Autodesk Fusion 360 part; units mm, degrees
(part 3 of 11)
  spline S15 degree 5 poles (-18.2968, 31.9705) (-18.3043, 31.9837) (-18.319, 32.0102) (-18.3401, 32.0504) (-18.3664, 32.105) (-18.3968, 32.1744) (-18.4253, 32.2448) (-18.4528, 32.3158) (-18.4796, 32.3871) (-18.5059, 32.4586) (-18.5319, 32.5304) (-18.5573, 32.6024) (-18.5819, 32.6748) (-18.6056, 32.7475) (-18.6285, 32.8208) (-18.6505, 32.8944) (-18.6718, 32.9683) (-18.6925, 33.0425) (-18.7127, 33.1169) (-18.7324, 33.1916) (-18.7516, 33.2664) (-18.7703, 33.3415) (-18.7884, 33.4168) (-18.806, 33.4924) (-18.823, 33.5682) (-18.8394, 33.6442) (-18.8554, 33.7204) (-18.8709, 33.7969) (-18.8859, 33.8735) (-18.9004, 33.9503) (-18.9145, 34.0272) (-18.9281, 34.1044) (-18.9413, 34.1817) (-18.954, 34.2592) (-18.9663, 34.3369) (-18.9781, 34.4148) (-18.9895, 34.4928) (-19.0005, 34.5709) (-19.011, 34.6492) (-19.0211, 34.7277) (-19.0308, 34.8063) (-19.0401, 34.8851) (-19.049, 34.964) (-19.0575, 35.043) (-19.0656, 35.1222) (-19.0732, 35.2015) (-19.0805, 35.281) (-19.0874, 35.3605) (-19.0939, 35.4402) (-19.1, 35.52) (-19.1058, 35.6) (-19.1111, 35.68) (-19.1161, 35.7602) (-19.1207, 35.8405) (-19.1249, 35.9209) (-19.1288, 36.0014) (-19.1323, 36.0821) (-19.1354, 36.1628) (-19.1382, 36.2436) (-19.1406, 36.3246) (-19.1426, 36.4056) (-19.1443, 36.4868) (-19.1456, 36.568) (-19.1466, 36.6493) (-19.1472, 36.7308) (-19.1475, 36.8123) (-19.1474, 36.8939) (-19.147, 36.9756) (-19.1463, 37.0574) (-19.1452, 37.1393) (-19.1437, 37.2212) (-19.1423, 37.2869) (-19.141, 37.3362) (-19.1402, 37.369) (-19.1397, 37.3855) knots 0 0 0 0 0 0 0.01428571 0.02857143 0.04285714 0.05714286 0.07142857 0.08571429 0.1 0.11428571 0.12857143 0.14285714 0.15714286 0.17142857 0.18571429 0.2 0.21428571 0.22857143 0.24285714 0.25714286 0.27142857 0.28571429 0.3 0.31428571 0.32857143 0.34285714 0.35714286 0.37142857 0.38571429 0.4 0.41428571 0.42857143 0.44285714 0.45714286 0.47142857 0.48571429 0.5 0.51428571 0.52857143 0.54285714 0.55714286 0.57142857 0.58571429 0.6 0.61428571 0.62857143 0.64285714 0.65714286 0.67142857 0.68571429 0.7 0.71428571 0.72857143 0.74285714 0.75714286 0.77142857 0.78571429 0.8 0.81428571 0.82857143 0.84285714 0.85714286 0.87142857 0.88571429 0.9 0.91428571 0.92857143 0.94285714 0.95714286 0.97142857 0.98571429 1 1 1 1 1 1
  line L15 (-18.2968, 31.9705) -> (-18.2665, 31.9176)
  arc A30 (-18.6146, 30.5673) -> (-18.2665, 31.9176) centre (-19.1347, 31.4214) ccw
  arc A31 (-18.6146, 30.5673) -> (-19.4636, 30.0339) centre (0, 0) ccw
  arc A32 (-20.8312, 30.3061) -> (-19.4636, 30.0339) centre (-20.0075, 30.8731) ccw
  line L16 (-20.8312, 30.3061) -> (-20.8658, 30.3563)
  spline S16 degree 5 poles (-20.8658, 30.3563) (-20.8744, 30.3688) (-20.8919, 30.3936) (-20.919, 30.43) (-20.9567, 30.4774) (-21.0061, 30.5349) (-21.0571, 30.5912) (-21.1092, 30.6467) (-21.1618, 30.7017) (-21.2148, 30.7566) (-21.2682, 30.8111) (-21.322, 30.8652) (-21.3765, 30.9188) (-21.4318, 30.9717) (-21.4879, 31.0241) (-21.5446, 31.0759) (-21.602, 31.1271) (-21.6599, 31.178) (-21.7182, 31.2284) (-21.7769, 31.2786) (-21.836, 31.3284) (-21.8955, 31.3778) (-21.9555, 31.4268) (-22.016, 31.4754) (-22.0769, 31.5236) (-22.1382, 31.5714) (-22.2, 31.6189) (-22.2621, 31.666) (-22.3247, 31.7127) (-22.3875, 31.7592) (-22.4508, 31.8053) (-22.5144, 31.851) (-22.5783, 31.8964) (-22.6427, 31.9415) (-22.7073, 31.9863) (-22.7723, 32.0307) (-22.8377, 32.0748) (-22.9033, 32.1186) (-22.9693, 32.1621) (-23.0356, 32.2052) (-23.1023, 32.2481) (-23.1692, 32.2906) (-23.2364, 32.3329) (-23.3039, 32.3748) (-23.3718, 32.4164) (-23.4399, 32.4578) (-23.5083, 32.4988) (-23.577, 32.5395) (-23.646, 32.58) (-23.7153, 32.6201) (-23.7848, 32.66) (-23.8546, 32.6995) (-23.9247, 32.7388) (-23.995, 32.7778) (-24.0656, 32.8165) (-24.1365, 32.8549) (-24.2076, 32.893) (-24.279, 32.9309) (-24.3506, 32.9684) (-24.4225, 33.0057) (-24.4947, 33.0427) (-24.567, 33.0794) (-24.6397, 33.1159) (-24.7125, 33.1521) (-24.7856, 33.188) (-24.8589, 33.2236) (-24.9325, 33.2589) (-25.0063, 33.294) (-25.0803, 33.3288) (-25.1546, 33.3633) (-25.229, 33.3976) (-25.2888, 33.4248) (-25.3337, 33.445) (-25.3637, 33.4585) (-25.3787, 33.4652) knots 0 0 0 0 0 0 0.01428571 0.02857143 0.04285714 0.05714286 0.07142857 0.08571429 0.1 0.11428571 0.12857143 0.14285714 0.15714286 0.17142857 0.18571429 0.2 0.21428571 0.22857143 0.24285714 0.25714286 0.27142857 0.28571429 0.3 0.31428571 0.32857143 0.34285714 0.35714286 0.37142857 0.38571429 0.4 0.41428571 0.42857143 0.44285714 0.45714286 0.47142857 0.48571429 0.5 0.51428571 0.52857143 0.54285714 0.55714286 0.57142857 0.58571429 0.6 0.61428571 0.62857143 0.64285714 0.65714286 0.67142857 0.68571429 0.7 0.71428571 0.72857143 0.74285714 0.75714286 0.77142857 0.78571429 0.8 0.81428571 0.82857143 0.84285714 0.85714286 0.87142857 0.88571429 0.9 0.91428571 0.92857143 0.94285714 0.95714286 0.97142857 0.98571429 1 1 1 1 1 1
  arc A33 (-25.3787, 33.4652) -> (-26.9789, 32.1891) centre (0, 0) ccw
  spline S17 degree 5 poles (-24.9521, 27.0976) (-24.9624, 27.1087) (-24.9826, 27.1313) (-25.0122, 27.1658) (-25.05, 27.2131) (-25.095, 27.2741) (-25.1385, 27.3364) (-25.1811, 27.3995) (-25.223, 27.463) (-25.2647, 27.5269) (-25.306, 27.591) (-25.3467, 27.6556) (-25.3868, 27.7207) (-25.4262, 27.7864) (-25.4647, 27.8526) (-25.5026, 27.9195) (-25.5398, 27.9868) (-25.5765, 28.0546) (-25.6127, 28.1226) (-25.6485, 28.191) (-25.6839, 28.2597) (-25.7188, 28.3288) (-25.7533, 28.3982) (-25.7872, 28.4679) (-25.8207, 28.538) (-25.8536, 28.6085) (-25.8862, 28.6793) (-25.9182, 28.7503) (-25.9499, 28.8217) (-25.9812, 28.8933) (-26.0121, 28.9652) (-26.0425, 29.0374) (-26.0726, 29.1099) (-26.1022, 29.1826) (-26.1315, 29.2556) (-26.1603, 29.3289) (-26.1888, 29.4024) (-26.2168, 29.4762) (-26.2445, 29.5502) (-26.2719, 29.6244) (-26.2988, 29.6989) (-26.3254, 29.7736) (-26.3516, 29.8486) (-26.3775, 29.9237) (-26.403, 29.9991) (-26.4281, 30.0747) (-26.4529, 30.1506) (-26.4773, 30.2266) (-26.5014, 30.3029) (-26.5251, 30.3793) (-26.5485, 30.456) (-26.5715, 30.5328) (-26.5942, 30.6099) (-26.6166, 30.6872) (-26.6386, 30.7646) (-26.6603, 30.8422) (-26.6816, 30.9201) (-26.7026, 30.9981) (-26.7233, 31.0763) (-26.7437, 31.1547) (-26.7637, 31.2332) (-26.7834, 31.312) (-26.8028, 31.3909) (-26.8218, 31.4699) (-26.8405, 31.5492) (-26.859, 31.6286) (-26.877, 31.7082) (-26.8948, 31.7879) (-26.9123, 31.8679) (-26.9294, 31.9479) (-26.9462, 32.0282) (-26.9594, 32.0925) (-26.9692, 32.1408) (-26.9757, 32.173) (-26.9789, 32.1891) knots 0 0 0 0 0 0 0.01428571 0.02857143 0.04285714 0.05714286 0.07142857 0.08571429 0.1 0.11428571 0.12857143 0.14285714 0.15714286 0.17142857 0.18571429 0.2 0.21428571 0.22857143 0.24285714 0.25714286 0.27142857 0.28571429 0.3 0.31428571 0.32857143 0.34285714 0.35714286 0.37142857 0.38571429 0.4 0.41428571 0.42857143 0.44285714 0.45714286 0.47142857 0.48571429 0.5 0.51428571 0.52857143 0.54285714 0.55714286 0.57142857 0.58571429 0.6 0.61428571 0.62857143 0.64285714 0.65714286 0.67142857 0.68571429 0.7 0.71428571 0.72857143 0.74285714 0.75714286 0.77142857 0.78571429 0.8 0.81428571 0.82857143 0.84285714 0.85714286 0.87142857 0.88571429 0.9 0.91428571 0.92857143 0.94285714 0.95714286 0.97142857 0.98571429 1 1 1 1 1 1
  line L17 (-24.9521, 27.0976) -> (-24.9108, 27.0527)
  arc A34 (-24.9498, 25.6588) -> (-24.9108, 27.0527) centre (-25.6469, 26.3758) ccw
  arc A35 (-24.9498, 25.6588) -> (-25.6588, 24.9498) centre (0, 0) ccw
  arc A36 (-27.0527, 24.9108) -> (-25.6588, 24.9498) centre (-26.3758, 25.6469) ccw
  line L18 (-27.0527, 24.9108) -> (-27.0976, 24.9521)
  spline S18 degree 5 poles (-27.0976, 24.9521) (-27.1087, 24.9624) (-27.1313, 24.9826) (-27.1658, 25.0122) (-27.2131, 25.05) (-27.2741, 25.095) (-27.3364, 25.1385) (-27.3995, 25.1811) (-27.463, 25.223) (-27.5269, 25.2647) (-27.591, 25.306) (-27.6556, 25.3467) (-27.7207, 25.3868) (-27.7864, 25.4262) (-27.8526, 25.4647) (-27.9195, 25.5026) (-27.9868, 25.5398) (-28.0546, 25.5765) (-28.1226, 25.6127) (-28.191, 25.6485) (-28.2597, 25.6839) (-28.3288, 25.7188) (-28.3982, 25.7533) (-28.4679, 25.7872) (-28.538, 25.8207) (-28.6085, 25.8536) (-28.6793, 25.8862) (-28.7503, 25.9182) (-28.8217, 25.9499) (-28.8933, 25.9812) (-28.9652, 26.0121) (-29.0374, 26.0425) (-29.1099, 26.0726) (-29.1826, 26.1022) (-29.2556, 26.1315) (-29.3289, 26.1603) (-29.4024, 26.1888) (-29.4762, 26.2168) (-29.5502, 26.2445) (-29.6244, 26.2719) (-29.6989, 26.2988) (-29.7736, 26.3254) (-29.8486, 26.3516) (-29.9237, 26.3775) (-29.9991, 26.403) (-30.0747, 26.4281) (-30.1506, 26.4529) (-30.2266, 26.4773) (-30.3029, 26.5014) (-30.3793, 26.5251) (-30.456, 26.5485) (-30.5328, 26.5715) (-30.6099, 26.5942) (-30.6872, 26.6166) (-30.7646, 26.6386) (-30.8422, 26.6603) (-30.9201, 26.6816) (-30.9981, 26.7026) (-31.0763, 26.7233) (-31.1547, 26.7437) (-31.2332, 26.7637) (-31.312, 26.7834) (-31.3909, 26.8028) (-31.4699, 26.8218) (-31.5492, 26.8405) (-31.6286, 26.859) (-31.7082, 26.877) (-31.7879, 26.8948) (-31.8679, 26.9123) (-31.9479, 26.9294) (-32.0282, 26.9462) (-32.0925, 26.9594) (-32.1408, 26.9692) (-32.173, 26.9757) (-32.1891, 26.9789) knots 0 0 0 0 0 0 0.01428571 0.02857143 0.04285714 0.05714286 0.07142857 0.08571429 0.1 0.11428571 0.12857143 0.14285714 0.15714286 0.17142857 0.18571429 0.2 0.21428571 0.22857143 0.24285714 0.25714286 0.27142857 0.28571429 0.3 0.31428571 0.32857143 0.34285714 0.35714286 0.37142857 0.38571429 0.4 0.41428571 0.42857143 0.44285714 0.45714286 0.47142857 0.48571429 0.5 0.51428571 0.52857143 0.54285714 0.55714286 0.57142857 0.58571429 0.6 0.61428571 0.62857143 0.64285714 0.65714286 0.67142857 0.68571429 0.7 0.71428571 0.72857143 0.74285714 0.75714286 0.77142857 0.78571429 0.8 0.81428571 0.82857143 0.84285714 0.85714286 0.87142857 0.88571429 0.9 0.91428571 0.92857143 0.94285714 0.95714286 0.97142857 0.98571429 1 1 1 1 1 1
  arc A37 (-32.1891, 26.9789) -> (-33.4652, 25.3787) centre (0, 0) ccw
  spline S19 degree 5 poles (-30.3563, 20.8658) (-30.3688, 20.8744) (-30.3936, 20.8919) (-30.43, 20.919) (-30.4774, 20.9567) (-30.5349, 21.0061) (-30.5912, 21.0571) (-30.6467, 21.1092) (-30.7017, 21.1618) (-30.7566, 21.2148) (-30.8111, 21.2682) (-30.8652, 21.322) (-30.9188, 21.3765) (-30.9717, 21.4318) (-31.0241, 21.4879) (-31.0759, 21.5446) (-31.1271, 21.602) (-31.178, 21.6599) (-31.2284, 21.7182) (-31.2786, 21.7769) (-31.3284, 21.836) (-31.3778, 21.8955) (-31.4268, 21.9555) (-31.4754, 22.016) (-31.5236, 22.0769) (-31.5714, 22.1382) (-31.6189, 22.2) (-31.666, 22.2621) (-31.7127, 22.3247) (-31.7592, 22.3875) (-31.8053, 22.4508) (-31.851, 22.5144) (-31.8964, 22.5783) (-31.9415, 22.6427) (-31.9863, 22.7073) (-32.0307, 22.7723) (-32.0748, 22.8377) (-32.1186, 22.9033) (-32.1621, 22.9693) (-32.2052, 23.0356) (-32.2481, 23.1023) (-32.2906, 23.1692) (-32.3329, 23.2364) (-32.3748, 23.3039) (-32.4164, 23.3718) (-32.4578, 23.4399) (-32.4988, 23.5083) (-32.5395, 23.577) (-32.58, 23.646) (-32.6201, 23.7153) (-32.66, 23.7848) (-32.6995, 23.8546) (-32.7388, 23.9247) (-32.7778, 23.995) (-32.8165, 24.0656) (-32.8549, 24.1365) (-32.893, 24.2076) (-32.9309, 24.279) (-32.9684, 24.3506) (-33.0057, 24.4225) (-33.0427, 24.4947) (-33.0794, 24.567) (-33.1159, 24.6397) (-33.1521, 24.7125) (-33.188, 24.7856) (-33.2236, 24.8589) (-33.2589, 24.9325) (-33.294, 25.0063) (-33.3288, 25.0803) (-33.3633, 25.1546) (-33.3976, 25.229) (-33.4248, 25.2888) (-33.445, 25.3337) (-33.4585, 25.3637) (-33.4652, 25.3787) knots 0 0 0 0 0 0 0.01428571 0.02857143 0.04285714 0.05714286 0.07142857 0.08571429 0.1 0.11428571 0.12857143 0.14285714 0.15714286 0.17142857 0.18571429 0.2 0.21428571 0.22857143 0.24285714 0.25714286 0.27142857 0.28571429 0.3 0.31428571 0.32857143 0.34285714 0.35714286 0.37142857 0.38571429 0.4 0.41428571 0.42857143 0.44285714 0.45714286 0.47142857 0.48571429 0.5 0.51428571 0.52857143 0.54285714 0.55714286 0.57142857 0.58571429 0.6 0.61428571 0.62857143 0.64285714 0.65714286 0.67142857 0.68571429 0.7 0.71428571 0.72857143 0.74285714 0.75714286 0.77142857 0.78571429 0.8 0.81428571 0.82857143 0.84285714 0.85714286 0.87142857 0.88571429 0.9 0.91428571 0.92857143 0.94285714 0.95714286 0.97142857 0.98571429 1 1 1 1 1 1
  line L19 (-30.3563, 20.8658) -> (-30.3061, 20.8312)
  arc A38 (-30.0339, 19.4636) -> (-30.3061, 20.8312) centre (-30.8731, 20.0075) ccw
  arc A39 (-30.0339, 19.4636) -> (-30.5673, 18.6146) centre (0, 0) ccw
  arc A40 (-31.9176, 18.2665) -> (-30.5673, 18.6146) centre (-31.4214, 19.1347) ccw
  line L20 (-31.9176, 18.2665) -> (-31.9705, 18.2968)
  spline S20 degree 5 poles (-31.9705, 18.2968) (-31.9837, 18.3043) (-32.0102, 18.319) (-32.0504, 18.3401) (-32.105, 18.3664) (-32.1744, 18.3968) (-32.2448, 18.4253) (-32.3158, 18.4528) (-32.3871, 18.4796) (-32.4586, 18.5059) (-32.5304, 18.5319) (-32.6024, 18.5573) (-32.6748, 18.5819) (-32.7475, 18.6056) (-32.8208, 18.6285) (-32.8944, 18.6505) (-32.9683, 18.6718) (-33.0425, 18.6925) (-33.1169, 18.7127) (-33.1916, 18.7324) (-33.2664, 18.7516) (-33.3415, 18.7703) (-33.4168, 18.7884) (-33.4924, 18.806) (-33.5682, 18.823) (-33.6442, 18.8394) (-33.7204, 18.8554) (-33.7969, 18.8709) (-33.8735, 18.8859) (-33.9503, 18.9004) (-34.0272, 18.9145) (-34.1044, 18.9281) (-34.1817, 18.9413) (-34.2592, 18.954) (-34.3369, 18.9663) (-34.4148, 18.9781) (-34.4928, 18.9895) (-34.5709, 19.0005) (-34.6492, 19.011) (-34.7277, 19.0211) (-34.8063, 19.0308) (-34.8851, 19.0401) (-34.964, 19.049) (-35.043, 19.0575) (-35.1222, 19.0656) (-35.2015, 19.0732) (-35.281, 19.0805) (-35.3605, 19.0874) (-35.4402, 19.0939) (-35.52, 19.1) (-35.6, 19.1058) (-35.68, 19.1111) (-35.7602, 19.1161) (-35.8405, 19.1207) (-35.9209, 19.1249) (-36.0014, 19.1288) (-36.0821, 19.1323) (-36.1628, 19.1354) (-36.2436, 19.1382) (-36.3246, 19.1406) (-36.4056, 19.1426) (-36.4868, 19.1443) (-36.568, 19.1456) (-36.6493, 19.1466) (-36.7308, 19.1472) (-36.8123, 19.1475) (-36.8939, 19.1474) (-36.9756, 19.147) (-37.0574, 19.1463) (-37.1393, 19.1452) (-37.2212, 19.1437) (-37.2869, 19.1423) (-37.3362, 19.141) (-37.369, 19.1402) (-37.3855, 19.1397) knots 0 0 0 0 0 0 0.01428571 0.02857143 0.04285714 0.05714286 0.07142857 0.08571429 0.1 0.11428571 0.12857143 0.14285714 0.15714286 0.17142857 0.18571429 0.2 0.21428571 0.22857143 0.24285714 0.25714286 0.27142857 0.28571429 0.3 0.31428571 0.32857143 0.34285714 0.35714286 0.37142857 0.38571429 0.4 0.41428571 0.42857143 0.44285714 0.45714286 0.47142857 0.48571429 0.5 0.51428571 0.52857143 0.54285714 0.55714286 0.57142857 0.58571429 0.6 0.61428571 0.62857143 0.64285714 0.65714286 0.67142857 0.68571429 0.7 0.71428571 0.72857143 0.74285714 0.75714286 0.77142857 0.78571429 0.8 0.81428571 0.82857143 0.84285714 0.85714286 0.87142857 0.88571429 0.9 0.91428571 0.92857143 0.94285714 0.95714286 0.97142857 0.98571429 1 1 1 1 1 1
  arc A41 (-37.3855, 19.1397) -> (-38.2735, 17.2957) centre (0, 0) ccw
  spline S21 degree 5 poles (-34.2383, 13.5877) (-34.2524, 13.5933) (-34.2804, 13.6049) (-34.322, 13.6232) (-34.3766, 13.6494) (-34.4436, 13.6848) (-34.5098, 13.722) (-34.5755, 13.7604) (-34.6409, 13.7995) (-34.7062, 13.8389) (-34.7712, 13.8788) (-34.8359, 13.9193) (-34.9003, 13.9605) (-34.9642, 14.0026) (-35.0278, 14.0456) (-35.0909, 14.0894) (-35.1536, 14.134) (-35.2161, 14.1791) (-35.2782, 14.2247) (-35.3402, 14.2708) (-35.4019, 14.3173) (-35.4633, 14.3644) (-35.5244, 14.412) (-35.5852, 14.4601) (-35.6458, 14.5087) (-35.7061, 14.5579) (-35.7661, 14.6075) (-35.8258, 14.6576) (-35.8853, 14.7082) (-35.9446, 14.7592) (-36.0036, 14.8106) (-36.0624, 14.8624) (-36.1209, 14.9146) (-36.1791, 14.9673) (-36.2372, 15.0204) (-36.295, 15.0739) (-36.3525, 15.1278) (-36.4098, 15.182) (-36.4669, 15.2367) (-36.5237, 15.2917) (-36.5803, 15.3472) (-36.6367, 15.4029) (-36.6928, 15.4591) (-36.7487, 15.5156) (-36.8044, 15.5725) (-36.8598, 15.6297) (-36.9151, 15.6872) (-36.9701, 15.7452) (-37.0248, 15.8034) (-37.0794, 15.862) (-37.1337, 15.9209) (-37.1878, 15.9802) (-37.2417, 16.0398) (-37.2954, 16.0997) (-37.3488, 16.1599) (-37.402, 16.2204) (-37.455, 16.2813) (-37.5078, 16.3425) (-37.5604, 16.404) (-37.6127, 16.4657) (-37.6648, 16.5278) (-37.7168, 16.5902) (-37.7684, 16.6529) (-37.8199, 16.7159) (-37.8712, 16.7792) (-37.9222, 16.8427) (-37.9731, 16.9066) (-38.0237, 16.9707) (-38.0741, 17.0352) (-38.1243, 17.0999) (-38.1742, 17.1648) (-38.214, 17.2171) (-38.2438, 17.2563) (-38.2636, 17.2826) (-38.2735, 17.2957) knots 0 0 0 0 0 0 0.01428571 0.02857143 0.04285714 0.05714286 0.07142857 0.08571429 0.1 0.11428571 0.12857143 0.14285714 0.15714286 0.17142857 0.18571429 0.2 0.21428571 0.22857143 0.24285714 0.25714286 0.27142857 0.28571429 0.3 0.31428571 0.32857143 0.34285714 0.35714286 0.37142857 0.38571429 0.4 0.41428571 0.42857143 0.44285714 0.45714286 0.47142857 0.48571429 0.5 0.51428571 0.52857143 0.54285714 0.55714286 0.57142857 0.58571429 0.6 0.61428571 0.62857143 0.64285714 0.65714286 0.67142857 0.68571429 0.7 0.71428571 0.72857143 0.74285714 0.75714286 0.77142857 0.78571429 0.8 0.81428571 0.82857143 0.84285714 0.85714286 0.87142857 0.88571429 0.9 0.91428571 0.92857143 0.94285714 0.95714286 0.97142857 0.98571429 1 1 1 1 1 1
  line L21 (-34.2383, 13.5877) -> (-34.1816, 13.5652)
  arc A42 (-33.6119, 12.2925) -> (-34.1816, 13.5652) centre (-34.5511, 12.636) ccw
  arc A43 (-33.6119, 12.2925) -> (-33.9431, 11.346) centre (0, 0) ccw
  arc A44 (-35.182, 10.7062) -> (-33.9431, 11.346) centre (-34.8915, 11.6631) ccw
  line L22 (-35.182, 10.7062) -> (-35.2404, 10.7239)
  spline S22 degree 5 poles (-35.2404, 10.7239) (-35.2549, 10.7283) (-35.284, 10.7368) (-35.3279, 10.7484) (-35.3869, 10.7619) (-35.4614, 10.7761) (-35.5364, 10.7882) (-35.6117, 10.7992) (-35.6872, 10.8094) (-35.7628, 10.8192) (-35.8385, 10.8286) (-35.9144, 10.8373) (-35.9904, 10.8452) (-36.0666, 10.8522) (-36.1431, 10.8581) (-36.2198, 10.8632) (-36.2966, 10.8675) (-36.3735, 10.8712) (-36.4506, 10.8743) (-36.5277, 10.8769) (-36.605, 10.879) (-36.6823, 10.8805) (-36.7598, 10.8814) (-36.8374, 10.8817) (-36.9151, 10.8814) (-36.9928, 10.8806) (-37.0707, 10.8792) (-37.1487, 10.8772) (-37.2267, 10.8748) (-37.3048, 10.8719) (-37.383, 10.8685) (-37.4612, 10.8646) (-37.5396, 10.8603) (-37.618, 10.8554) (-37.6964, 10.8501) (-37.7749, 10.8443) (-37.8535, 10.838) (-37.9322, 10.8313) (-38.0109, 10.8242) (-38.0896, 10.8166) (-38.1684, 10.8086) (-38.2473, 10.8001) (-38.3262, 10.7912) (-38.4051, 10.7819) (-38.4841, 10.7721) (-38.5631, 10.762) (-38.6422, 10.7514) (-38.7213, 10.7404) (-38.8005, 10.729) (-38.8796, 10.7172) (-38.9589, 10.705) (-39.0381, 10.6924) (-39.1174, 10.6794) (-39.1967, 10.666) (-39.276, 10.6523) (-39.3554, 10.6381) (-39.4347, 10.6236) (-39.5142, 10.6087) (-39.5936, 10.5934) (-39.673, 10.5777) (-39.7525, 10.5617) (-39.832, 10.5453) (-39.9115, 10.5285) (-39.991, 10.5113) (-40.0705, 10.4938) (-40.1501, 10.4759) (-40.2296, 10.4577) (-40.3092, 10.4391) (-40.3887, 10.4202) (-40.4683, 10.4009) (-40.5479, 10.3812) (-40.6116, 10.3652) (-40.6593, 10.3531) (-40.6912, 10.3449) (-40.7071, 10.3408) knots 0 0 0 0 0 0 0.01428571 0.02857143 0.04285714 0.05714286 0.07142857 0.08571429 0.1 0.11428571 0.12857143 0.14285714 0.15714286 0.17142857 0.18571429 0.2 0.21428571 0.22857143 0.24285714 0.25714286 0.27142857 0.28571429 0.3 0.31428571 0.32857143 0.34285714 0.35714286 0.37142857 0.38571429 0.4 0.41428571 0.42857143 0.44285714 0.45714286 0.47142857 0.48571429 0.5 0.51428571 0.52857143 0.54285714 0.55714286 0.57142857 0.58571429 0.6 0.61428571 0.62857143 0.64285714 0.65714286 0.67142857 0.68571429 0.7 0.71428571 0.72857143 0.74285714 0.75714286 0.77142857 0.78571429 0.8 0.81428571 0.82857143 0.84285714 0.85714286 0.87142857 0.88571429 0.9 0.91428571 0.92857143 0.94285714 0.95714286 0.97142857 0.98571429 1 1 1 1 1 1
  arc A45 (-40.7071, 10.3408) -> (-41.1625, 8.3454) centre (0, 0) ccw
  spline S23 degree 5 poles (-36.4034, 5.6283) (-36.4184, 5.6307) (-36.4483, 5.6357) (-36.4929, 5.6442) (-36.552, 5.6577) (-36.6252, 5.6772) (-36.698, 5.6988) (-36.7706, 5.7216) (-36.8431, 5.7451) (-36.9154, 5.7691) (-36.9877, 5.7935) (-37.0598, 5.8186) (-37.1318, 5.8445) (-37.2035, 5.8713) (-37.275, 5.8991) (-37.3463, 5.9277) (-37.4173, 5.9572) (-37.4883, 5.9873) (-37.559, 6.0179) (-37.6297, 6.049) (-37.7002, 6.0807) (-37.7705, 6.1129) (-37.8407, 6.1457) (-37.9107, 6.1791) (-37.9806, 6.213) (-38.0503, 6.2475) (-38.1198, 6.2826) (-38.1892, 6.3182) (-38.2585, 6.3542) (-38.3276, 6.3907) (-38.3966, 6.4277) (-38.4654, 6.4651) (-38.5341, 6.503) (-38.6026, 6.5414) (-38.671, 6.5803) (-38.7392, 6.6196) (-38.8073, 6.6593) (-38.8752, 6.6995) (-38.943, 6.74) (-39.0107, 6.7811) (-39.0782, 6.8225) (-39.1456, 6.8643) (-39.2128, 6.9066) (-39.2799, 6.9492) (-39.3468, 6.9923) (-39.4136, 7.0357) (-39.4803, 7.0796) (-39.5468, 7.1238) (-39.6131, 7.1684) (-39.6794, 7.2134) (-39.7454, 7.2587) (-39.8114, 7.3045) (-39.8772, 7.3506) (-39.9428, 7.397) (-40.0083, 7.4438) (-40.0737, 7.491) (-40.1389, 7.5386) (-40.204, 7.5865) (-40.2689, 7.6347) (-40.3337, 7.6833) (-40.3983, 7.7322) (-40.4628, 7.7815) (-40.5271, 7.8311) (-40.5913, 7.8811) (-40.6554, 7.9313) (-40.7193, 7.982) (-40.7831, 8.0329) (-40.8467, 8.0842) (-40.9101, 8.1358) (-40.9735, 8.1877) (-41.0366, 8.2399) (-41.0871, 8.282) (-41.1248, 8.3136) (-41.15, 8.3348) (-41.1625, 8.3454) knots 0 0 0 0 0 0 0.01428571 0.02857143 0.04285714 0.05714286 0.07142857 0.08571429 0.1 0.11428571 0.12857143 0.14285714 0.15714286 0.17142857 0.18571429 0.2 0.21428571 0.22857143 0.24285714 0.25714286 0.27142857 0.28571429 0.3 0.31428571 0.32857143 0.34285714 0.35714286 0.37142857 0.38571429 0.4 0.41428571 0.42857143 0.44285714 0.45714286 0.47142857 0.48571429 0.5 0.51428571 0.52857143 0.54285714 0.55714286 0.57142857 0.58571429 0.6 0.61428571 0.62857143 0.64285714 0.65714286 0.67142857 0.68571429 0.7 0.71428571 0.72857143 0.74285714 0.75714286 0.77142857 0.78571429 0.8 0.81428571 0.82857143 0.84285714 0.85714286 0.87142857 0.88571429 0.9 0.91428571 0.92857143 0.94285714 0.95714286 0.97142857 0.98571429 1 1 1 1 1 1
  line L23 (-36.4034, 5.6283) -> (-36.3431, 5.619)
  arc A46 (-35.5045, 4.5049) -> (-36.3431, 5.619) centre (-36.4966, 4.6308) ccw
  arc A47 (-35.5045, 4.5049) -> (-35.6168, 3.5085) centre (0, 0) ccw
  arc A48 (-36.6823, 2.609) -> (-35.6168, 3.5085) centre (-36.612, 3.6066) ccw
  line L24 (-36.6823, 2.609) -> (-36.7431, 2.6133)
  spline S24 degree 5 poles (-36.7431, 2.6133) (-36.7583, 2.6144) (-36.7885, 2.6161) (-36.8339, 2.6177) (-36.8945, 2.6178) (-36.9702, 2.615) (-37.0461, 2.6101) (-37.1219, 2.6041) (-37.1978, 2.5973) (-37.2736, 2.59) (-37.3495, 2.5823) (-37.4254, 2.5739) (-37.5013, 2.5647) (-37.5772, 2.5545) (-37.6531, 2.5433) (-37.7289, 2.5312) (-37.8048, 2.5183) (-37.8806, 2.5048) (-37.9564, 2.4907) (-38.0322, 2.476) (-38.108, 2.4608) (-38.1838, 2.4451) (-38.2595, 2.4287) (-38.3352, 2.4118) (-38.4109, 2.3942) (-38.4865, 2.3761) (-38.5621, 2.3574) (-38.6377, 2.3382) (-38.7132, 2.3184) (-38.7887, 2.2982) (-38.8642, 2.2775) (-38.9396, 2.2563) (-39.015, 2.2346) (-39.0904, 2.2125) (-39.1657, 2.1898) (-39.2409, 2.1667) (-39.3162, 2.1431) (-39.3913, 2.1191) (-39.4665, 2.0946) (-39.5415, 2.0697) (-39.6166, 2.0443) (-39.6916, 2.0185) (-39.7665, 1.9923) (-39.8414, 1.9656) (-39.9162, 1.9385) (-39.991, 1.911) (-40.0658, 1.8831) (-40.1405, 1.8548) (-40.2151, 1.8261) (-40.2896, 1.797) (-40.3642, 1.7675) (-40.4386, 1.7375) (-40.513, 1.7072) (-40.5874, 1.6765) (-40.6616, 1.6455) (-40.7359, 1.614) (-40.81, 1.5822) (-40.8841, 1.55) (-40.9581, 1.5174) (-41.0321, 1.4844) (-41.106, 1.4511) (-41.1798, 1.4174) (-41.2536, 1.3834) (-41.3273, 1.349) (-41.401, 1.3142) (-41.4745, 1.2791) (-41.548, 1.2436) (-41.6215, 1.2078) (-41.6948, 1.1716) (-41.7681, 1.1351) (-41.8413, 1.0982) (-41.8998, 1.0684) (-41.9437, 1.0459) (-41.9729, 1.0309) (-41.9875, 1.0233) knots 0 0 0 0 0 0 0.01428571 0.02857143 0.04285714 0.05714286 0.07142857 0.08571429 0.1 0.11428571 0.12857143 0.14285714 0.15714286 0.17142857 0.18571429 0.2 0.21428571 0.22857143 0.24285714 0.25714286 0.27142857 0.28571429 0.3 0.31428571 0.32857143 0.34285714 0.35714286 0.37142857 0.38571429 0.4 0.41428571 0.42857143 0.44285714 0.45714286 0.47142857 0.48571429 0.5 0.51428571 0.52857143 0.54285714 0.55714286 0.57142857 0.58571429 0.6 0.61428571 0.62857143 0.64285714 0.65714286 0.67142857 0.68571429 0.7 0.71428571 0.72857143 0.74285714 0.75714286 0.77142857 0.78571429 0.8 0.81428571 0.82857143 0.84285714 0.85714286 0.87142857 0.88571429 0.9 0.91428571 0.92857143 0.94285714 0.95714286 0.97142857 0.98571429 1 1 1 1 1 1
  arc A49 (-41.9875, 1.0233) -> (-41.9875, -1.0233) centre (0, 0) ccw
  spline S25 degree 5 poles (-36.7431, -2.6133) (-36.7583, -2.6144) (-36.7885, -2.6161) (-36.8339, -2.6177) (-36.8945, -2.6178) (-36.9702, -2.615) (-37.0461, -2.6101) (-37.1219, -2.6041) (-37.1978, -2.5973) (-37.2736, -2.59) (-37.3495, -2.5823) (-37.4254, -2.5739) (-37.5013, -2.5647) (-37.5772, -2.5545) (-37.6531, -2.5433) (-37.7289, -2.5312) (-37.8048, -2.5183) (-37.8806, -2.5048) (-37.9564, -2.4907) (-38.0322, -2.476) (-38.108, -2.4608) (-38.1838, -2.4451) (-38.2595, -2.4287) (-38.3352, -2.4118) (-38.4109, -2.3942) (-38.4865, -2.3761) (-38.5621, -2.3574) (-38.6377, -2.3382) (-38.7132, -2.3184) (-38.7887, -2.2982) (-38.8642, -2.2775) (-38.9396, -2.2563) (-39.015, -2.2346) (-39.0904, -2.2125) (-39.1657, -2.1898) (-39.2409, -2.1667) (-39.3162, -2.1431) (-39.3913, -2.1191) (-39.4665, -2.0946) (-39.5415, -2.0697) (-39.6166, -2.0443) (-39.6916, -2.0185) (-39.7665, -1.9923) (-39.8414, -1.9656) (-39.9162, -1.9385) (-39.991, -1.911) (-40.0658, -1.8831) (-40.1405, -1.8548) (-40.2151, -1.8261) (-40.2896, -1.797) (-40.3642, -1.7675) (-40.4386, -1.7375) (-40.513, -1.7072) (-40.5874, -1.6765) (-40.6616, -1.6455) (-40.7359, -1.614) (-40.81, -1.5822) (-40.8841, -1.55) (-40.9581, -1.5174) (-41.0321, -1.4844) (-41.106, -1.4511) (-41.1798, -1.4174) (-41.2536, -1.3834) (-41.3273, -1.349) (-41.401, -1.3142) (-41.4745, -1.2791) (-41.548, -1.2436) (-41.6215, -1.2078) (-41.6948, -1.1716) (-41.7681, -1.1351) (-41.8413, -1.0982) (-41.8998, -1.0684) (-41.9437, -1.0459) (-41.9729, -1.0309) (-41.9875, -1.0233) knots 0 0 0 0 0 0 0.01428571 0.02857143 0.04285714 0.05714286 0.07142857 0.08571429 0.1 0.11428571 0.12857143 0.14285714 0.15714286 0.17142857 0.18571429 0.2 0.21428571 0.22857143 0.24285714 0.25714286 0.27142857 0.28571429 0.3 0.31428571 0.32857143 0.34285714 0.35714286 0.37142857 0.38571429 0.4 0.41428571 0.42857143 0.44285714 0.45714286 0.47142857 0.48571429 0.5 0.51428571 0.52857143 0.54285714 0.55714286 0.57142857 0.58571429 0.6 0.61428571 0.62857143 0.64285714 0.65714286 0.67142857 0.68571429 0.7 0.71428571 0.72857143 0.74285714 0.75714286 0.77142857 0.78571429 0.8 0.81428571 0.82857143 0.84285714 0.85714286 0.87142857 0.88571429 0.9 0.91428571 0.92857143 0.94285714 0.95714286 0.97142857 0.98571429 1 1 1 1 1 1
  line L25 (-36.7431, -2.6133) -> (-36.6823, -2.609)
  arc A50 (-35.6168, -3.5085) -> (-36.6823, -2.609) centre (-36.612, -3.6066) ccw
  arc A51 (-35.6168, -3.5085) -> (-35.5045, -4.5049) centre (0, 0) ccw
  arc A52 (-36.3431, -5.619) -> (-35.5045, -4.5049) centre (-36.4966, -4.6308) ccw
  line L26 (-36.3431, -5.619) -> (-36.4034, -5.6283)
  spline S26 degree 5 poles (-36.4034, -5.6283) (-36.4184, -5.6307) (-36.4483, -5.6357) (-36.4929, -5.6442) (-36.552, -5.6577) (-36.6252, -5.6772) (-36.698, -5.6988) (-36.7706, -5.7216) (-36.8431, -5.7451) (-36.9154, -5.7691) (-36.9877, -5.7935) (-37.0598, -5.8186) (-37.1318, -5.8445) (-37.2035, -5.8713) (-37.275, -5.8991) (-37.3463, -5.9277) (-37.4173, -5.9572) (-37.4883, -5.9873) (-37.559, -6.0179) (-37.6297, -6.049) (-37.7002, -6.0807) (-37.7705, -6.1129) (-37.8407, -6.1457) (-37.9107, -6.1791) (-37.9806, -6.213) (-38.0503, -6.2475) (-38.1198, -6.2826) (-38.1892, -6.3182) (-38.2585, -6.3542) (-38.3276, -6.3907) (-38.3966, -6.4277) (-38.4654, -6.4651) (-38.5341, -6.503) (-38.6026, -6.5414) (-38.671, -6.5803) (-38.7392, -6.6196) (-38.8073, -6.6593) (-38.8752, -6.6995) (-38.943, -6.74) (-39.0107, -6.7811) (-39.0782, -6.8225) (-39.1456, -6.8643) (-39.2128, -6.9066) (-39.2799, -6.9492) (-39.3468, -6.9923) (-39.4136, -7.0357) (-39.4803, -7.0796) (-39.5468, -7.1238) (-39.6131, -7.1684) (-39.6794, -7.2134) (-39.7454, -7.2587) (-39.8114, -7.3045) (-39.8772, -7.3506) (-39.9428, -7.397) (-40.0083, -7.4438) (-40.0737, -7.491) (-40.1389, -7.5386) (-40.204, -7.5865) (-40.2689, -7.6347) (-40.3337, -7.6833) (-40.3983, -7.7322) (-40.4628, -7.7815) (-40.5271, -7.8311) (-40.5913, -7.8811) (-40.6554, -7.9313) (-40.7193, -7.982) (-40.7831, -8.0329) (-40.8467, -8.0842) (-40.9101, -8.1358) (-40.9735, -8.1877) (-41.0366, -8.2399) (-41.0871, -8.282) (-41.1248, -8.3136) (-41.15, -8.3348) (-41.1625, -8.3454) knots 0 0 0 0 0 0 0.01428571 0.02857143 0.04285714 0.05714286 0.07142857 0.08571429 0.1 0.11428571 0.12857143 0.14285714 0.15714286 0.17142857 0.18571429 0.2 0.21428571 0.22857143 0.24285714 0.25714286 0.27142857 0.28571429 0.3 0.31428571 0.32857143 0.34285714 0.35714286 0.37142857 0.38571429 0.4 0.41428571 0.42857143 0.44285714 0.45714286 0.47142857 0.48571429 0.5 0.51428571 0.52857143 0.54285714 0.55714286 0.57142857 0.58571429 0.6 0.61428571 0.62857143 0.64285714 0.65714286 0.67142857 0.68571429 0.7 0.71428571 0.72857143 0.74285714 0.75714286 0.77142857 0.78571429 0.8 0.81428571 0.82857143 0.84285714 0.85714286 0.87142857 0.88571429 0.9 0.91428571 0.92857143 0.94285714 0.95714286 0.97142857 0.98571429 1 1 1 1 1 1
  arc A53 (-41.1625, -8.3454) -> (-40.7071, -10.3408) centre (0, 0) ccw
  spline S27 degree 5 poles (-35.2404, -10.7239) (-35.2549, -10.7283) (-35.284, -10.7368) (-35.3279, -10.7484) (-35.3869, -10.7619) (-35.4614, -10.7761) (-35.5364, -10.7882) (-35.6117, -10.7992) (-35.6872, -10.8094) (-35.7628, -10.8192) (-35.8385, -10.8286) (-35.9144, -10.8373) (-35.9904, -10.8452) (-36.0666, -10.8522) (-36.1431, -10.8581) (-36.2198, -10.8632) (-36.2966, -10.8675) (-36.3735, -10.8712) (-36.4506, -10.8743) (-36.5277, -10.8769) (-36.605, -10.879) (-36.6823, -10.8805) (-36.7598, -10.8814) (-36.8374, -10.8817) (-36.9151, -10.8814) (-36.9928, -10.8806) (-37.0707, -10.8792) (-37.1487, -10.8772) (-37.2267, -10.8748) (-37.3048, -10.8719) (-37.383, -10.8685) (-37.4612, -10.8646) (-37.5396, -10.8603) (-37.618, -10.8554) (-37.6964, -10.8501) (-37.7749, -10.8443) (-37.8535, -10.838) (-37.9322, -10.8313) (-38.0109, -10.8242) (-38.0896, -10.8166) (-38.1684, -10.8086) (-38.2473, -10.8001) (-38.3262, -10.7912) (-38.4051, -10.7819) (-38.4841, -10.7721) (-38.5631, -10.762) (-38.6422, -10.7514) (-38.7213, -10.7404) (-38.8005, -10.729) (-38.8796, -10.7172) (-38.9589, -10.705) (-39.0381, -10.6924) (-39.1174, -10.6794) (-39.1967, -10.666) (-39.276, -10.6523) (-39.3554, -10.6381) (-39.4347, -10.6236) (-39.5142, -10.6087) (-39.5936, -10.5934) (-39.673, -10.5777) (-39.7525, -10.5617) (-39.832, -10.5453) (-39.9115, -10.5285) (-39.991, -10.5113) (-40.0705, -10.4938) (-40.1501, -10.4759) (-40.2296, -10.4577) (-40.3092, -10.4391) (-40.3887, -10.4202) (-40.4683, -10.4009) (-40.5479, -10.3812) (-40.6116, -10.3652) (-40.6593, -10.3531) (-40.6912, -10.3449) (-40.7071, -10.3408) knots 0 0 0 0 0 0 0.01428571 0.02857143 0.04285714 0.05714286 0.07142857 0.08571429 0.1 0.11428571 0.12857143 0.14285714 0.15714286 0.17142857 0.18571429 0.2 0.21428571 0.22857143 0.24285714 0.25714286 0.27142857 0.28571429 0.3 0.31428571 0.32857143 0.34285714 0.35714286 0.37142857 0.38571429 0.4 0.41428571 0.42857143 0.44285714 0.45714286 0.47142857 0.48571429 0.5 0.51428571 0.52857143 0.54285714 0.55714286 0.57142857 0.58571429 0.6 0.61428571 0.62857143 0.64285714 0.65714286 0.67142857 0.68571429 0.7 0.71428571 0.72857143 0.74285714 0.75714286 0.77142857 0.78571429 0.8 0.81428571 0.82857143 0.84285714 0.85714286 0.87142857 0.88571429 0.9 0.91428571 0.92857143 0.94285714 0.95714286 0.97142857 0.98571429 1 1 1 1 1 1
  line L27 (-35.2404, -10.7239) -> (-35.182, -10.7062)
  arc A54 (-33.9431, -11.346) -> (-35.182, -10.7062) centre (-34.8915, -11.6631) ccw
  arc A55 (-33.9431, -11.346) -> (-33.6119, -12.2925) centre (0, 0) ccw
  arc A56 (-34.1816, -13.5652) -> (-33.6119, -12.2925) centre (-34.5511, -12.636) ccw
  line L28 (-34.1816, -13.5652) -> (-34.2383, -13.5877)
  spline S28 degree 5 poles (-34.2383, -13.5877) (-34.2524, -13.5933) (-34.2804, -13.6049) (-34.322, -13.6232) (-34.3766, -13.6494) (-34.4436, -13.6848) (-34.5098, -13.722) (-34.5755, -13.7604) (-34.6409, -13.7995) (-34.7062, -13.8389) (-34.7712, -13.8788) (-34.8359, -13.9193) (-34.9003, -13.9605) (-34.9642, -14.0026) (-35.0278, -14.0456) (-35.0909, -14.0894) (-35.1536, -14.134) (-35.2161, -14.1791) (-35.2782, -14.2247) (-35.3402, -14.2708) (-35.4019, -14.3173) (-35.4633, -14.3644) (-35.5244, -14.412) (-35.5852, -14.4601) (-35.6458, -14.5087) (-35.7061, -14.5579) (-35.7661, -14.6075) (-35.8258, -14.6576) (-35.8853, -14.7082) (-35.9446, -14.7592) (-36.0036, -14.8106) (-36.0624, -14.8624) (-36.1209, -14.9146) (-36.1791, -14.9673) (-36.2372, -15.0204) (-36.295, -15.0739) (-36.3525, -15.1278) (-36.4098, -15.182) (-36.4669, -15.2367) (-36.5237, -15.2917) (-36.5803, -15.3472) (-36.6367, -15.4029) (-36.6928, -15.4591) (-36.7487, -15.5156) (-36.8044, -15.5725) (-36.8598, -15.6297) (-36.9151, -15.6872) (-36.9701, -15.7452) (-37.0248, -15.8034) (-37.0794, -15.862) (-37.1337, -15.9209) (-37.1878, -15.9802) (-37.2417, -16.0398) (-37.2954, -16.0997) (-37.3488, -16.1599) (-37.402, -16.2204) (-37.455, -16.2813) (-37.5078, -16.3425) (-37.5604, -16.404) (-37.6127, -16.4657) (-37.6648, -16.5278) (-37.7168, -16.5902) (-37.7684, -16.6529) (-37.8199, -16.7159) (-37.8712, -16.7792) (-37.9222, -16.8427) (-37.9731, -16.9066) (-38.0237, -16.9707) (-38.0741, -17.0352) (-38.1243, -17.0999) (-38.1742, -17.1648) (-38.214, -17.2171) (-38.2438, -17.2563) (-38.2636, -17.2826) (-38.2735, -17.2957) knots 0 0 0 0 0 0 0.01428571 0.02857143 0.04285714 0.05714286 0.07142857 0.08571429 0.1 0.11428571 0.12857143 0.14285714 0.15714286 0.17142857 0.18571429 0.2 0.21428571 0.22857143 0.24285714 0.25714286 0.27142857 0.28571429 0.3 0.31428571 0.32857143 0.34285714 0.35714286 0.37142857 0.38571429 0.4 0.41428571 0.42857143 0.44285714 0.45714286 0.47142857 0.48571429 0.5 0.51428571 0.52857143 0.54285714 0.55714286 0.57142857 0.58571429 0.6 0.61428571 0.62857143 0.64285714 0.65714286 0.67142857 0.68571429 0.7 0.71428571 0.72857143 0.74285714 0.75714286 0.77142857 0.78571429 0.8 0.81428571 0.82857143 0.84285714 0.85714286 0.87142857 0.88571429 0.9 0.91428571 0.92857143 0.94285714 0.95714286 0.97142857 0.98571429 1 1 1 1 1 1
  arc A57 (-38.2735, -17.2957) -> (-37.3855, -19.1397) centre (0, 0) ccw
  spline S29 degree 5 poles (-31.9705, -18.2968) (-31.9837, -18.3043) (-32.0102, -18.319) (-32.0504, -18.3401) (-32.105, -18.3664) (-32.1744, -18.3968) (-32.2448, -18.4253) (-32.3158, -18.4528) (-32.3871, -18.4796) (-32.4586, -18.5059) (-32.5304, -18.5319) (-32.6024, -18.5573) (-32.6748, -18.5819) (-32.7475, -18.6056) (-32.8208, -18.6285) (-32.8944, -18.6505) (-32.9683, -18.6718) (-33.0425, -18.6925) (-33.1169, -18.7127) (-33.1916, -18.7324) (-33.2664, -18.7516) (-33.3415, -18.7703) (-33.4168, -18.7884) (-33.4924, -18.806) (-33.5682, -18.823) (-33.6442, -18.8394) (-33.7204, -18.8554) (-33.7969, -18.8709) (-33.8735, -18.8859) (-33.9503, -18.9004) (-34.0272, -18.9145) (-34.1044, -18.9281) (-34.1817, -18.9413) (-34.2592, -18.954) (-34.3369, -18.9663) (-34.4148, -18.9781) (-34.4928, -18.9895) (-34.5709, -19.0005) (-34.6492, -19.011) (-34.7277, -19.0211) (-34.8063, -19.0308) (-34.8851, -19.0401) (-34.964, -19.049) (-35.043, -19.0575) (-35.1222, -19.0656) (-35.2015, -19.0732) (-35.281, -19.0805) (-35.3605, -19.0874) (-35.4402, -19.0939) (-35.52, -19.1) (-35.6, -19.1058) (-35.68, -19.1111) (-35.7602, -19.1161) (-35.8405, -19.1207) (-35.9209, -19.1249) (-36.0014, -19.1288) (-36.0821, -19.1323) (-36.1628, -19.1354) (-36.2436, -19.1382) (-36.3246, -19.1406) (-36.4056, -19.1426) (-36.4868, -19.1443) (-36.568, -19.1456) (-36.6493, -19.1466) (-36.7308, -19.1472) (-36.8123, -19.1475) (-36.8939, -19.1474) (-36.9756, -19.147) (-37.0574, -19.1463) (-37.1393, -19.1452) (-37.2212, -19.1437) (-37.2869, -19.1423) (-37.3362, -19.141) (-37.369, -19.1402) (-37.3855, -19.1397) knots 0 0 0 0 0 0 0.01428571 0.02857143 0.04285714 0.05714286 0.07142857 0.08571429 0.1 0.11428571 0.12857143 0.14285714 0.15714286 0.17142857 0.18571429 0.2 0.21428571 0.22857143 0.24285714 0.25714286 0.27142857 0.28571429 0.3 0.31428571 0.32857143 0.34285714 0.35714286 0.37142857 0.38571429 0.4 0.41428571 0.42857143 0.44285714 0.45714286 0.47142857 0.48571429 0.5 0.51428571 0.52857143 0.54285714 0.55714286 0.57142857 0.58571429 0.6 0.61428571 0.62857143 0.64285714 0.65714286 0.67142857 0.68571429 0.7 0.71428571 0.72857143 0.74285714 0.75714286 0.77142857 0.78571429 0.8 0.81428571 0.82857143 0.84285714 0.85714286 0.87142857 0.88571429 0.9 0.91428571 0.92857143 0.94285714 0.95714286 0.97142857 0.98571429 1 1 1 1 1 1
  line L29 (-31.9705, -18.2968) -> (-31.9176, -18.2665)
  arc A58 (-30.5673, -18.6146) -> (-31.9176, -18.2665) centre (-31.4214, -19.1347) ccw
  arc A59 (-30.5673, -18.6146) -> (-30.0339, -19.4636) centre (0, 0) ccw
  arc A60 (-30.3061, -20.8312) -> (-30.0339, -19.4636) centre (-30.8731, -20.0075) ccw
  line L30 (-30.3061, -20.8312) -> (-30.3563, -20.8658)
  spline S30 degree 5 poles (-30.3563, -20.8658) (-30.3688, -20.8744) (-30.3936, -20.8919) (-30.43, -20.919) (-30.4774, -20.9567) (-30.5349, -21.0061) (-30.5912, -21.0571) (-30.6467, -21.1092) (-30.7017, -21.1618) (-30.7566, -21.2148) (-30.8111, -21.2682) (-30.8652, -21.322) (-30.9188, -21.3765) (-30.9717, -21.4318) (-31.0241, -21.4879) (-31.0759, -21.5446) (-31.1271, -21.602) (-31.178, -21.6599) (-31.2284, -21.7182) (-31.2786, -21.7769) (-31.3284, -21.836) (-31.3778, -21.8955) (-31.4268, -21.9555) (-31.4754, -22.016) (-31.5236, -22.0769) (-31.5714, -22.1382) (-31.6189, -22.2) (-31.666, -22.2621) (-31.7127, -22.3247) (-31.7592, -22.3875) (-31.8053, -22.4508) (-31.851, -22.5144) (-31.8964, -22.5783) (-31.9415, -22.6427) (-31.9863, -22.7073) (-32.0307, -22.7723) (-32.0748, -22.8377) (-32.1186, -22.9033) (-32.1621, -22.9693) (-32.2052, -23.0356) (-32.2481, -23.1023) (-32.2906, -23.1692) (-32.3329, -23.2364) (-32.3748, -23.3039) (-32.4164, -23.3718) (-32.4578, -23.4399) (-32.4988, -23.5083) (-32.5395, -23.577) (-32.58, -23.646) (-32.6201, -23.7153) (-32.66, -23.7848) (-32.6995, -23.8546) (-32.7388, -23.9247) (-32.7778, -23.995) (-32.8165, -24.0656) (-32.8549, -24.1365) (-32.893, -24.2076) (-32.9309, -24.279) (-32.9684, -24.3506) (-33.0057, -24.4225) (-33.0427, -24.4947) (-33.0794, -24.567) (-33.1159, -24.6397) (-33.1521, -24.7125) (-33.188, -24.7856) (-33.2236, -24.8589) (-33.2589, -24.9325) (-33.294, -25.0063) (-33.3288, -25.0803) (-33.3633, -25.1546) (-33.3976, -25.229) (-33.4248, -25.2888) (-33.445, -25.3337) (-33.4585, -25.3637) (-33.4652, -25.3787) knots 0 0 0 0 0 0 0.01428571 0.02857143 0.04285714 0.05714286 0.07142857 0.08571429 0.1 0.11428571 0.12857143 0.14285714 0.15714286 0.17142857 0.18571429 0.2 0.21428571 0.22857143 0.24285714 0.25714286 0.27142857 0.28571429 0.3 0.31428571 0.32857143 0.34285714 0.35714286 0.37142857 0.38571429 0.4 0.41428571 0.42857143 0.44285714 0.45714286 0.47142857 0.48571429 0.5 0.51428571 0.52857143 0.54285714 0.55714286 0.57142857 0.58571429 0.6 0.61428571 0.62857143 0.64285714 0.65714286 0.67142857 0.68571429 0.7 0.71428571 0.72857143 0.74285714 0.75714286 0.77142857 0.78571429 0.8 0.81428571 0.82857143 0.84285714 0.85714286 0.87142857 0.88571429 0.9 0.91428571 0.92857143 0.94285714 0.95714286 0.97142857 0.98571429 1 1 1 1 1 1
  arc A61 (-33.4652, -25.3787) -> (-32.1891, -26.9789) centre (0, 0) ccw
  spline S31 degree 5 poles (-27.0976, -24.9521) (-27.1087, -24.9624) (-27.1313, -24.9826) (-27.1658, -25.0122) (-27.2131, -25.05) (-27.2741, -25.095) (-27.3364, -25.1385) (-27.3995, -25.1811) (-27.463, -25.223) (-27.5269, -25.2647) (-27.591, -25.306) (-27.6556, -25.3467) (-27.7207, -25.3868) (-27.7864, -25.4262) (-27.8526, -25.4647) (-27.9195, -25.5026) (-27.9868, -25.5398) (-28.0546, -25.5765) (-28.1226, -25.6127) (-28.191, -25.6485) (-28.2597, -25.6839) (-28.3288, -25.7188) (-28.3982, -25.7533) (-28.4679, -25.7872) (-28.538, -25.8207) (-28.6085, -25.8536) (-28.6793, -25.8862) (-28.7503, -25.9182) (-28.8217, -25.9499) (-28.8933, -25.9812) (-28.9652, -26.0121) (-29.0374, -26.0425) (-29.1099, -26.0726) (-29.1826, -26.1022) (-29.2556, -26.1315) (-29.3289, -26.1603) (-29.4024, -26.1888) (-29.4762, -26.2168) (-29.5502, -26.2445) (-29.6244, -26.2719) (-29.6989, -26.2988) (-29.7736, -26.3254) (-29.8486, -26.3516) (-29.9237, -26.3775) (-29.9991, -26.403) (-30.0747, -26.4281) (-30.1506, -26.4529) (-30.2266, -26.4773) (-30.3029, -26.5014) (-30.3793, -26.5251) (-30.456, -26.5485) (-30.5328, -26.5715) (-30.6099, -26.5942) (-30.6872, -26.6166) (-30.7646, -26.6386) (-30.8422, -26.6603) (-30.9201, -26.6816) (-30.9981, -26.7026) (-31.0763, -26.7233) (-31.1547, -26.7437) (-31.2332, -26.7637) (-31.312, -26.7834) (-31.3909, -26.8028) (-31.4699, -26.8218) (-31.5492, -26.8405) (-31.6286, -26.859) (-31.7082, -26.877) (-31.7879, -26.8948) (-31.8679, -26.9123) (-31.9479, -26.9294) (-32.0282, -26.9462) (-32.0925, -26.9594) (-32.1408, -26.9692) (-32.173, -26.9757) (-32.1891, -26.9789) knots 0 0 0 0 0 0 0.01428571 0.02857143 0.04285714 0.05714286 0.07142857 0.08571429 0.1 0.11428571 0.12857143 0.14285714 0.15714286 0.17142857 0.18571429 0.2 0.21428571 0.22857143 0.24285714 0.25714286 0.27142857 0.28571429 0.3 0.31428571 0.32857143 0.34285714 0.35714286 0.37142857 0.38571429 0.4 0.41428571 0.42857143 0.44285714 0.45714286 0.47142857 0.48571429 0.5 0.51428571 0.52857143 0.54285714 0.55714286 0.57142857 0.58571429 0.6 0.61428571 0.62857143 0.64285714 0.65714286 0.67142857 0.68571429 0.7 0.71428571 0.72857143 0.74285714 0.75714286 0.77142857 0.78571429 0.8 0.81428571 0.82857143 0.84285714 0.85714286 0.87142857 0.88571429 0.9 0.91428571 0.92857143 0.94285714 0.95714286 0.97142857 0.98571429 1 1 1 1 1 1
  line L31 (-27.0976, -24.9521) -> (-27.0527, -24.9108)
  arc A62 (-25.6588, -24.9498) -> (-27.0527, -24.9108) centre (-26.3758, -25.6469) ccw
  arc A63 (-25.6588, -24.9498) -> (-24.9498, -25.6588) centre (0, 0) ccw
  arc A64 (-24.9108, -27.0527) -> (-24.9498, -25.6588) centre (-25.6469, -26.3758) ccw
  line L32 (-24.9108, -27.0527) -> (-24.9521, -27.0976)
  spline S32 degree 5 poles (-24.9521, -27.0976) (-24.9624, -27.1087) (-24.9826, -27.1313) (-25.0122, -27.1658) (-25.05, -27.2131) (-25.095, -27.2741) (-25.1385, -27.3364) (-25.1811, -27.3995) (-25.223, -27.463) (-25.2647, -27.5269) (-25.306, -27.591) (-25.3467, -27.6556) (-25.3868, -27.7207) (-25.4262, -27.7864) (-25.4647, -27.8526) (-25.5026, -27.9195) (-25.5398, -27.9868) (-25.5765, -28.0546) (-25.6127, -28.1226) (-25.6485, -28.191) (-25.6839, -28.2597) (-25.7188, -28.3288) (-25.7533, -28.3982) (-25.7872, -28.4679) (-25.8207, -28.538) (-25.8536, -28.6085) (-25.8862, -28.6793) (-25.9182, -28.7503) (-25.9499, -28.8217) (-25.9812, -28.8933) (-26.0121, -28.9652) (-26.0425, -29.0374) (-26.0726, -29.1099) (-26.1022, -29.1826) (-26.1315, -29.2556) (-26.1603, -29.3289) (-26.1888, -29.4024) (-26.2168, -29.4762) (-26.2445, -29.5502) (-26.2719, -29.6244) (-26.2988, -29.6989) (-26.3254, -29.7736) (-26.3516, -29.8486) (-26.3775, -29.9237) (-26.403, -29.9991) (-26.4281, -30.0747) (-26.4529, -30.1506) (-26.4773, -30.2266) (-26.5014, -30.3029) (-26.5251, -30.3793) (-26.5485, -30.456) (-26.5715, -30.5328) (-26.5942, -30.6099) (-26.6166, -30.6872) (-26.6386, -30.7646) (-26.6603, -30.8422) (-26.6816, -30.9201) (-26.7026, -30.9981) (-26.7233, -31.0763) (-26.7437, -31.1547) (-26.7637, -31.2332) (-26.7834, -31.312) (-26.8028, -31.3909) (-26.8218, -31.4699) (-26.8405, -31.5492) (-26.859, -31.6286) (-26.877, -31.7082) (-26.8948, -31.7879) (-26.9123, -31.8679) (-26.9294, -31.9479) (-26.9462, -32.0282) (-26.9594, -32.0925) (-26.9692, -32.1408) (-26.9757, -32.173) (-26.9789, -32.1891) knots 0 0 0 0 0 0 0.01428571 0.02857143 0.04285714 0.05714286 0.07142857 0.08571429 0.1 0.11428571 0.12857143 0.14285714 0.15714286 0.17142857 0.18571429 0.2 0.21428571 0.22857143 0.24285714 0.25714286 0.27142857 0.28571429 0.3 0.31428571 0.32857143 0.34285714 0.35714286 0.37142857 0.38571429 0.4 0.41428571 0.42857143 0.44285714 0.45714286 0.47142857 0.48571429 0.5 0.51428571 0.52857143 0.54285714 0.55714286 0.57142857 0.58571429 0.6 0.61428571 0.62857143 0.64285714 0.65714286 0.67142857 0.68571429 0.7 0.71428571 0.72857143 0.74285714 0.75714286 0.77142857 0.78571429 0.8 0.81428571 0.82857143 0.84285714 0.85714286 0.87142857 0.88571429 0.9 0.91428571 0.92857143 0.94285714 0.95714286 0.97142857 0.98571429 1 1 1 1 1 1
  arc A65 (-26.9789, -32.1891) -> (-25.3787, -33.4652) centre (0, 0) ccw
  spline S33 degree 5 poles (-20.8658, -30.3563) (-20.8744, -30.3688) (-20.8919, -30.3936) (-20.919, -30.43) (-20.9567, -30.4774) (-21.0061, -30.5349) (-21.0571, -30.5912) (-21.1092, -30.6467) (-21.1618, -30.7017) (-21.2148, -30.7566) (-21.2682, -30.8111) (-21.322, -30.8652) (-21.3765, -30.9188) (-21.4318, -30.9717) (-21.4879, -31.0241) (-21.5446, -31.0759) (-21.602, -31.1271) (-21.6599, -31.178) (-21.7182, -31.2284) (-21.7769, -31.2786) (-21.836, -31.3284) (-21.8955, -31.3778) (-21.9555, -31.4268) (-22.016, -31.4754) (-22.0769, -31.5236) (-22.1382, -31.5714) (-22.2, -31.6189) (-22.2621, -31.666) (-22.3247, -31.7127) (-22.3875, -31.7592) (-22.4508, -31.8053) (-22.5144, -31.851) (-22.5783, -31.8964) (-22.6427, -31.9415) (-22.7073, -31.9863) (-22.7723, -32.0307) (-22.8377, -32.0748) (-22.9033, -32.1186) (-22.9693, -32.1621) (-23.0356, -32.2052) (-23.1023, -32.2481) (-23.1692, -32.2906) (-23.2364, -32.3329) (-23.3039, -32.3748) (-23.3718, -32.4164) (-23.4399, -32.4578) (-23.5083, -32.4988) (-23.577, -32.5395) (-23.646, -32.58) (-23.7153, -32.6201) (-23.7848, -32.66) (-23.8546, -32.6995) (-23.9247, -32.7388) (-23.995, -32.7778) (-24.0656, -32.8165) (-24.1365, -32.8549) (-24.2076, -32.893) (-24.279, -32.9309) (-24.3506, -32.9684) (-24.4225, -33.0057) (-24.4947, -33.0427) (-24.567, -33.0794) (-24.6397, -33.1159) (-24.7125, -33.1521) (-24.7856, -33.188) (-24.8589, -33.2236) (-24.9325, -33.2589) (-25.0063, -33.294) (-25.0803, -33.3288) (-25.1546, -33.3633) (-25.229, -33.3976) (-25.2888, -33.4248) (-25.3337, -33.445) (-25.3637, -33.4585) (-25.3787, -33.4652) knots 0 0 0 0 0 0 0.01428571 0.02857143 0.04285714 0.05714286 0.07142857 0.08571429 0.1 0.11428571 0.12857143 0.14285714 0.15714286 0.17142857 0.18571429 0.2 0.21428571 0.22857143 0.24285714 0.25714286 0.27142857 0.28571429 0.3 0.31428571 0.32857143 0.34285714 0.35714286 0.37142857 0.38571429 0.4 0.41428571 0.42857143 0.44285714 0.45714286 0.47142857 0.48571429 0.5 0.51428571 0.52857143 0.54285714 0.55714286 0.57142857 0.58571429 0.6 0.61428571 0.62857143 0.64285714 0.65714286 0.67142857 0.68571429 0.7 0.71428571 0.72857143 0.74285714 0.75714286 0.77142857 0.78571429 0.8 0.81428571 0.82857143 0.84285714 0.85714286 0.87142857 0.88571429 0.9 0.91428571 0.92857143 0.94285714 0.95714286 0.97142857 0.98571429 1 1 1 1 1 1
  line L33 (-20.8658, -30.3563) -> (-20.8312, -30.3061)
  arc A66 (-19.4636, -30.0339) -> (-20.8312, -30.3061) centre (-20.0075, -30.8731) ccw
  arc A67 (-19.4636, -30.0339) -> (-18.6146, -30.5673) centre (0, 0) ccw
  arc A68 (-18.2665, -31.9176) -> (-18.6146, -30.5673) centre (-19.1347, -31.4214) ccw
  line L34 (-18.2665, -31.9176) -> (-18.2968, -31.9705)
  spline S34 degree 5 poles (-18.2968, -31.9705) (-18.3043, -31.9837) (-18.319, -32.0102) (-18.3401, -32.0504) (-18.3664, -32.105) (-18.3968, -32.1744) (-18.4253, -32.2448) (-18.4528, -32.3158) (-18.4796, -32.3871) (-18.5059, -32.4586) (-18.5319, -32.5304) (-18.5573, -32.6024) (-18.5819, -32.6748) (-18.6056, -32.7475) (-18.6285, -32.8208) (-18.6505, -32.8944) (-18.6718, -32.9683) (-18.6925, -33.0425) (-18.7127, -33.1169) (-18.7324, -33.1916) (-18.7516, -33.2664) (-18.7703, -33.3415) (-18.7884, -33.4168) (-18.806, -33.4924) (-18.823, -33.5682) (-18.8394, -33.6442) (-18.8554, -33.7204) (-18.8709, -33.7969) (-18.8859, -33.8735) (-18.9004, -33.9503) (-18.9145, -34.0272) (-18.9281, -34.1044) (-18.9413, -34.1817) (-18.954, -34.2592) (-18.9663, -34.3369) (-18.9781, -34.4148) (-18.9895, -34.4928) (-19.0005, -34.5709) (-19.011, -34.6492) (-19.0211, -34.7277) (-19.0308, -34.8063) (-19.0401, -34.8851) (-19.049, -34.964) (-19.0575, -35.043) (-19.0656, -35.1222) (-19.0732, -35.2015) (-19.0805, -35.281) (-19.0874, -35.3605) (-19.0939, -35.4402) (-19.1, -35.52) (-19.1058, -35.6) (-19.1111, -35.68) (-19.1161, -35.7602) (-19.1207, -35.8405) (-19.1249, -35.9209) (-19.1288, -36.0014) (-19.1323, -36.0821) (-19.1354, -36.1628) (-19.1382, -36.2436) (-19.1406, -36.3246) (-19.1426, -36.4056) (-19.1443, -36.4868) (-19.1456, -36.568) (-19.1466, -36.6493) (-19.1472, -36.7308) (-19.1475, -36.8123) (-19.1474, -36.8939) (-19.147, -36.9756) (-19.1463, -37.0574) (-19.1452, -37.1393) (-19.1437, -37.2212) (-19.1423, -37.2869) (-19.141, -37.3362) (-19.1402, -37.369) (-19.1397, -37.3855) knots 0 0 0 0 0 0 0.01428571 0.02857143 0.04285714 0.05714286 0.07142857 0.08571429 0.1 0.11428571 0.12857143 0.14285714 0.15714286 0.17142857 0.18571429 0.2 0.21428571 0.22857143 0.24285714 0.25714286 0.27142857 0.28571429 0.3 0.31428571 0.32857143 0.34285714 0.35714286 0.37142857 0.38571429 0.4 0.41428571 0.42857143 0.44285714 0.45714286 0.47142857 0.48571429 0.5 0.51428571 0.52857143 0.54285714 0.55714286 0.57142857 0.58571429 0.6 0.61428571 0.62857143 0.64285714 0.65714286 0.67142857 0.68571429 0.7 0.71428571 0.72857143 0.74285714 0.75714286 0.77142857 0.78571429 0.8 0.81428571 0.82857143 0.84285714 0.85714286 0.87142857 0.88571429 0.9 0.91428571 0.92857143 0.94285714 0.95714286 0.97142857 0.98571429 1 1 1 1 1 1
  arc A69 (-19.1397, -37.3855) -> (-17.2957, -38.2735) centre (0, 0) ccw